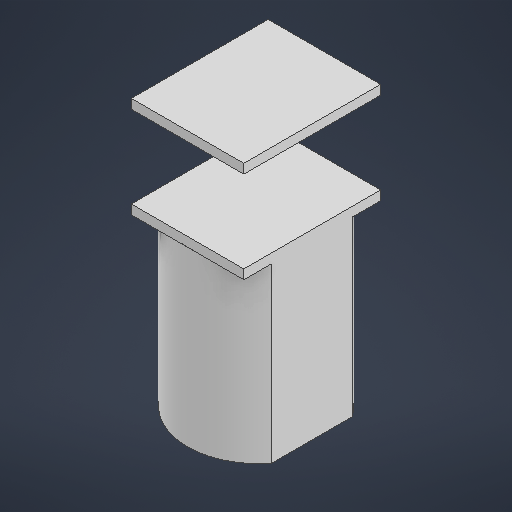
# Autodesk Inventor part: Motor
Saved by Autodesk Inventor 2026.2 (Build 302298000, 298)
## iProperties
Created: 2026-11-10
Part Number: Motor
Material: Generic
Document SubType Name: Modeling
Designer: Carro
Density: 1 g/cm^3
Appearance: Default
Author: Carro
Autodesk Inventor part; units mm, degrees
ref_plane "YZ Plane" through (0, 0, 0) normal (1, 0, 0) x (0, 1, 0)
ref_plane "XZ Plane" through (0, 0, 0) normal (0, 1, 0) x (-1, 0, 0)
sketch "Sketch1" plane through (0, 0, 0) normal (0, 1, 0) x (-1, 0, 0)
  line L0 (-4.9594, 3.556) -> (-4.9594, -3.556)
  line L1 (-4.9594, -3.556) -> (4.9594, -3.556)
  line L2 (4.9594, -3.556) -> (4.9594, 3.556)
  line L3 (4.9594, 3.556) -> (-4.9594, 3.556)
  line L4 (-4.9594, 3.556) -> (4.9594, -3.556) construction
  line L5 (-4.9594, -3.556) -> (4.9594, 3.556) construction
  line L6 (0, 6.0325) -> (0, -6.0325)
  arc A0 (4.9594, 3.556) -> (-4.9594, 3.556) centre (0, -0.1715) ccw
  arc A1 (-4.9594, -3.556) -> (4.9594, -3.556) centre (0, 0.1715) ccw
  point P0 (0, 0)
  dimension "d0" = 7.112
  dimension "d1" = 9.9187
  dimension "d2" = 12.065
  constraints: 14 end point, 6 point on circle, 3 midpoint, 2 centre point, 2 parallel, 2 vertical, 1 perpendicular
  measures "d0" distance of L0.start L0.end
  measures "d1" distance of L1.end L0.end
  measures "d2" distance of L6.start L6.end
extrude "Extrusion1" add sketch "Sketch1" along normal mid plane 15.24
ref_plane "Work Plane1" through (0, 16.51, 0) normal (0, 1, 0) x (1, 0, 0)
sketch "Sketch3" plane through (0, 16.51, 0) normal (0, 1, 0) x (1, 0, 0)
  line L0 (-4.9594, 3.556) -> (-4.9594, -3.556) projected
  line L1 (4.9594, -3.556) -> (4.9594, 3.556) projected
  arc A0 (4.9594, 3.556) -> (-4.9594, 3.556) centre (0, -0.1715) ccw projected
  arc A1 (-4.9594, -3.556) -> (4.9594, -3.556) centre (0, 0.1715) ccw projected
  line L2 (4.9594, -6.0325) -> (-4.9594, -6.0325)
  line L3 (-4.9594, -6.0325) -> (-4.9594, 6.0325)
  line L4 (-4.9594, 6.0325) -> (4.9594, 6.0325)
  line L5 (4.9594, 6.0325) -> (4.9594, -6.0325)
  line L6 (4.9594, -6.0325) -> (-4.9594, 6.0325) construction
  line L7 (-4.9594, -6.0325) -> (4.9594, 6.0325) construction
  point P0 (0, 0)
  constraints: 12 end point, 2 midpoint, 2 parallel, 1 collinear, 1 perpendicular, 1 tangent
extrude "Extrusion2" add sketch "Sketch3" against normal blind 0.8255
sketch "Sketch4" plane through (0, 7.62, 0) normal (0, 1, 0) x (1, 0, 0)
  line L0 (-4.9594, -6.0325) -> (-4.9594, 6.0325) projected
  line L1 (4.9594, -6.0325) -> (-4.9594, -6.0325) projected
  line L2 (-4.9594, 6.0325) -> (4.9594, 6.0325)
  line L3 (4.9594, 6.0325) -> (4.9594, -6.0325)
  line L4 (4.9594, -6.0325) -> (-4.9594, -6.0325)
  line L5 (-4.9594, -6.0325) -> (-4.9594, 6.0325)
  point P0 (0, 0)
  constraints: 8 end point, 2 parallel, 1 horizontal, 1 perpendicular
extrude "Extrusion3" add sketch "Sketch4" along normal blind 0.8255
sketch "Sketch5" plane through (0, -7.62, 0) normal (0, -1, 0) x (1, 0, 0)
  circle A0 centre (0, 0) radius 2.1502
  constraints: 1 centre point, 1 coincident
extrude "Extrusion4" add sketch "Sketch5" along normal blind 1.016
body "Solid1"
